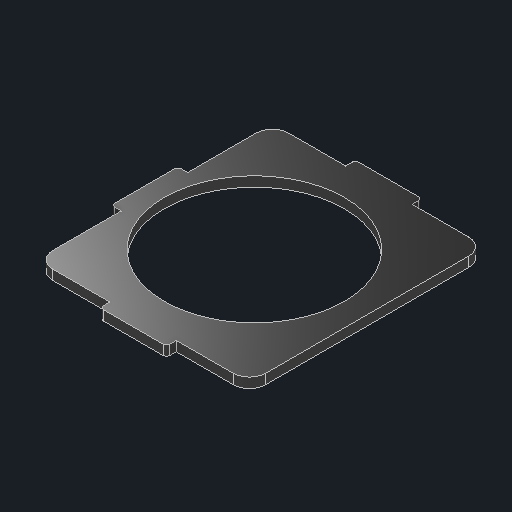
# Autodesk Inventor part: SlotCeiling
Saved by Autodesk Inventor 2027.1 (Build 311270010, 270A)
## iProperties
Created: 2026-10-20
Part Number: SlotCeiling
Material: MDF Medium Density Fiberboard
Document SubType Name: Modeling
Designer: SDS Scholar
Density: 0.8 g/cm^3
Appearance: Glossy - Black
Mass: 5.91389 g
Surface Area: 62.8913 cm^2
Volume: 7.39237 cm^3
Author: SDS Scholar
Autodesk Inventor part; units mm, degrees
ref_plane "YZ Plane" through (0, 0, 0) normal (1, 0, 0) x (0, 1, 0)
ref_plane "XZ Plane" through (0, 0, 0) normal (0, 1, 0) x (-1, 0, 0)
ref_plane "XY Plane" through (0, 0, 0) normal (0, 0, 1) x (1, 0, 0)
sketch "Sketch1" plane through (0, 0, 0) normal (0, 1, 0) x (-1, 0, 0)
  line L0 (32.5, 36) -> (-32.5, 36)
  line L1 (-32.5, 36) -> (-32.5, -36)
  line L2 (-32.5, -36) -> (32.5, -36)
  line L3 (32.5, -36) -> (32.5, 36)
  line L4 (10.15, 36) -> (-10.15, 36)
  line L5 (-10.15, 36) -> (-10.15, 39)
  line L6 (-10.15, 39) -> (10.15, 39)
  line L7 (10.15, 39) -> (10.15, 36)
  line L8 (32.5, 0) -> (-32.5, 0) construction
  line L9 (32.5, 10.15) -> (35.5, 10.15)
  line L10 (35.5, 10.15) -> (35.5, -10.15)
  line L11 (35.5, -10.15) -> (32.5, -10.15)
  line L12 (32.5, -10.15) -> (32.5, 10.15)
  line L13 (10.15, -36) -> (-10.15, -36)
  line L14 (-10.15, -36) -> (-10.15, -39)
  line L15 (-10.15, -39) -> (10.15, -39)
  line L16 (10.15, -39) -> (10.15, -36)
  line L17 (0, 36) -> (0, -36) construction
  circle A0 centre (2, 0) radius 27.5
  point P0 (0, 0)
  point P1 (0, 39)
  point P2 (0, 0)
  point P3 (35.5, 0)
  point P4 (-10.15, 36)
  point P5 (-10.15, -36)
  point P6 (10.15, -36)
  point P7 (32.5, -10.15)
  dimension "d2" = 72
  dimension "d3" = 65
  dimension "d4" = 3
  dimension "d5" = 20.3
  dimension "d6" = 3
  dimension "d7" = 20.3
  dimension "d14" = 55
  dimension "d15" = 34.5
  constraints: 36 end point, 7 midpoint, 6 parallel, 4 symmetric about line, 3 horizontal, 3 perpendicular, 3 point on line, 2 horizontal alignment, 2 vertical alignment, 1 centre point, 1 vertical
  measures "d2" distance of L0.end L1.end
  measures "d3" distance of L1.end L2.end
  measures "d4" distance of L6.end L4.start
  measures "d5" distance of L5.end L6.end
  measures "d6" distance of L9.start L9.end
  measures "d7" distance of L9.end L10.end
  measures "d14" diameter of A0
  measures "d15" distance from line of L1 A0.centre
extrude "Extrusion1" add sketch "Sketch1" along normal blind 3
fillet "Fillet1" radius 5 4 edges at (32.5, 1.5, 36) (32.5, 1.5, -36) (-32.5, 1.5, -36) (-32.5, 1.5, 36)
fillet "Fillet2" radius 1 6 edges at (-35.5, 1.5, -10.15) (-35.5, 1.5, 10.15) (-10.15, 1.5, 39) (-10.15, 1.5, -39) (10.15, 1.5, -39) (10.15, 1.5, 39)
equation "\"GridProcutClearance\" = 5"
equation "\"GridBorderThickness\" = 5"
equation "\"GridBorderFillets\" = 7"
equation "\"GridTotalSize\" = 65"
equation "\"GridRobotClearance\" = 65"
equation "\"AluminiumExtrusionClearance\" = 35"
equation "\"BaseTotalLength\" = 885"
equation "\"WorkspaceLength\" = 515"
equation "\"WorkspaceHeight\" = 183"
equation "\"AxesBaseFillet\" = 15"
equation "\"Zaxis\" = 197"
equation "\"ProductTotalHeight\" = 45"
equation "\"VerticalStroke\" = 105"
equation "\"BackArea\" = 165"
equation "\"CylinderStroke\" = 75"
equation "\"BoxesWidth\" = 125"
equation "\"BaseWoodThickness\" = 7"
equation "\"Kerf\" = 0.3"
equation "\"RxThickness\" = 1.8"
equation "\"support_2\" = 265"
body "Solid1"
